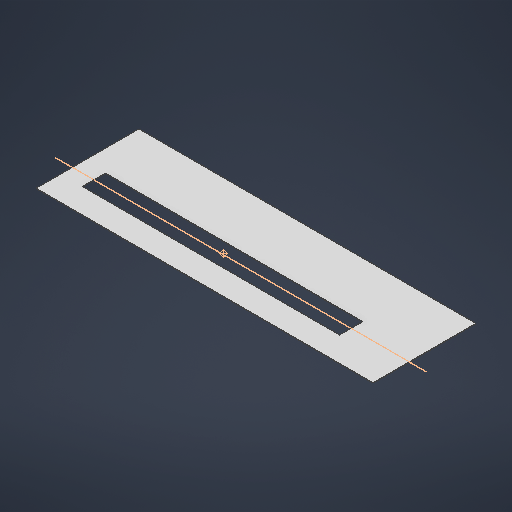
# Autodesk Inventor part: Papel_v0
Saved by Autodesk Inventor 2027 (Build 310192060, 192F)
## iProperties
Created: 2026-10-12
Part Number: Papel_v0
Material: Generic
Document SubType Name: Modeling
Designer: Pablo
Density: 1 g/cm^3
Appearance: Default
Author: Pablo
Autodesk Inventor part; units mm, degrees
ref_plane "YZ Plane" through (0, 0, 0) normal (1, 0, 0) x (0, 1, 0)
ref_plane "XZ Plane" through (0, 0, 0) normal (0, 1, 0) x (-1, 0, 0)
sketch "Sketch1" plane through (0, 0, 0) normal (0, 1, 0) x (-1, 0, 0)
  line L0 (-327.5, -100) -> (327.5, -100)
  line L1 (327.5, -100) -> (327.5, 100)
  line L2 (327.5, 100) -> (-327.5, 100)
  line L3 (-327.5, 100) -> (-327.5, -100)
  line L4 (-327.5, -100) -> (327.5, 100) construction
  line L5 (327.5, -100) -> (-327.5, 100) construction
  line L6 (-214.5, 100) -> (-214.5, 52) construction
  line L7 (-327.5, 52) -> (-214.5, 52) construction
  line L8 (-214.5, 52) -> (285.5, 52)
  line L9 (285.5, 52) -> (285.5, 7)
  line L10 (285.5, 7) -> (-214.5, 7)
  line L11 (-214.5, 7) -> (-214.5, 52)
  point P0 (0, 0)
  dimension "d6" = 200
  dimension "d13" = 48
  dimension "d14" = 113
  dimension "d15" = 500
  dimension "d16" = 45
  dimension "d17" = 655
  constraints: 24 end point, 5 parallel, 3 horizontal, 2 midpoint, 2 perpendicular, 2 point on line
  measures "d6" distance of L0.end L1.end
  measures "d13" distance of L6.end L6.start
  measures "d14" distance of L7.start L6.end
  measures "d15" distance of L9.end L10.end
  measures "d16" distance of L8.end L9.end
  measures "d17" distance of L1.end L2.end
extrude "Extrusion1" add sketch "Sketch1" along normal blind 1
ref_plane "Work Plane1" through (-35.5, 1, 29.5) normal (0, 0, 1) x (1, 0, 0)
body "Solid1"
